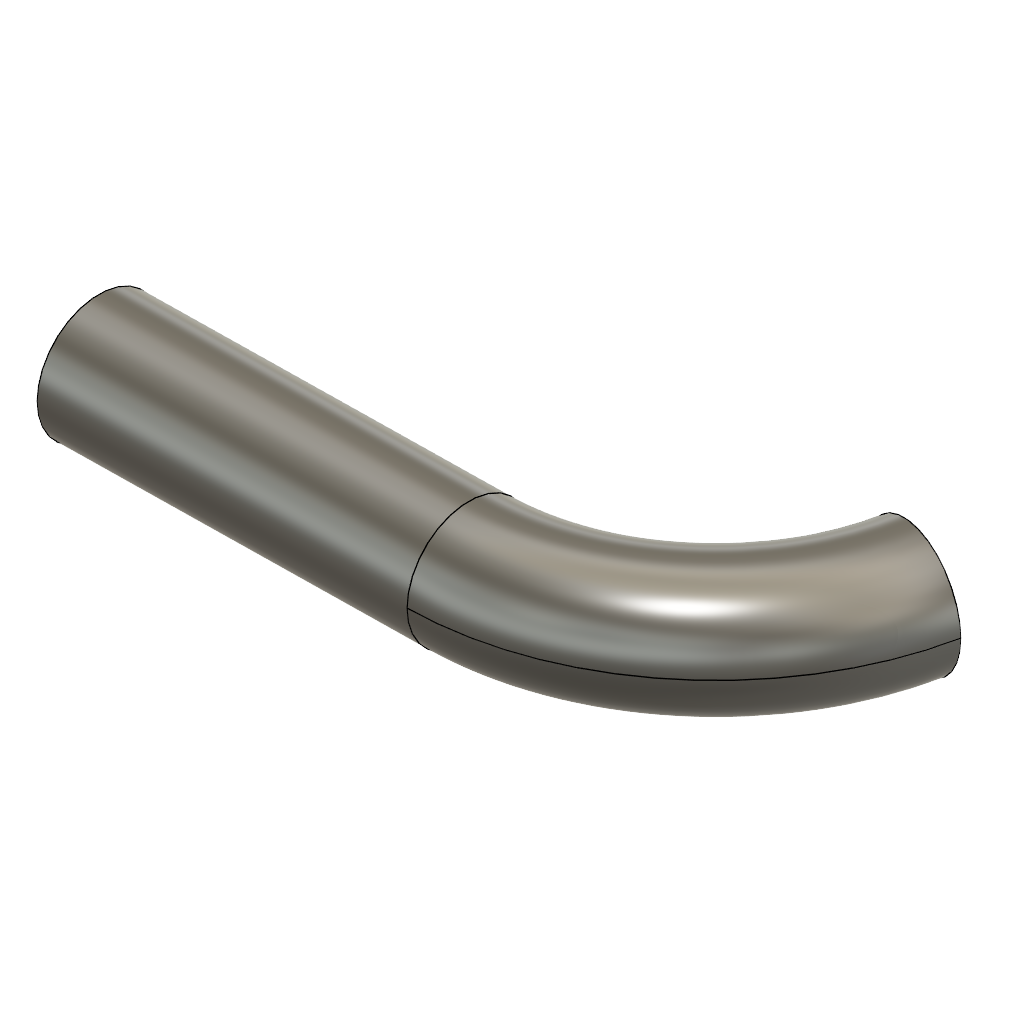
sweep_line_arc_path (Autodesk Fusion 360 design; units mm, degrees)
part number: 2026-11-13-14-38-42-277
Autodesk Fusion 360 part; units mm, degrees
sketch "Sketch1" plane through (0, 0, 0) normal (1, 0, 0) x (0, 0, -1)
  circle A0 centre (0, 0) radius 3
sketch "Sketch2" plane through (0, 0, 0) normal (0, 1, 0) x (1, 0, 0)
  line L0 (0, -0.5298) -> (17.7043, -0.2459)
  arc A0 (17.7043, -0.2459) -> (30, 10) centre (17.5, 12.5) ccw
  constraint tangent L0 A0
sweep "Sweep1" add profiles "Sketch1" path "Sketch2" along L0 A0 section 1
